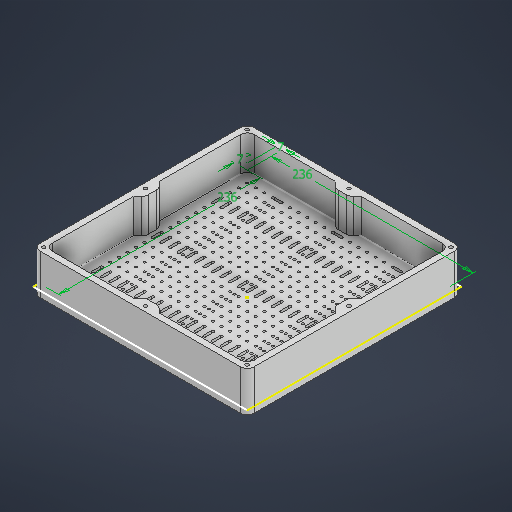
# Autodesk Inventor part: Part1
Saved by Autodesk Inventor 2027.2 (Build 312334000, 334)
## iProperties
Created: 2026-11-18
Part Number: Part1
Material: Generic
Document SubType Name: Modeling
Designer: Brian Wang
Density: 1 g/cm^3
Appearance: Default
Author: Brian Wang
Autodesk Inventor part; units mm, degrees
ref_plane "YZ Plane" through (0, 0, 0) normal (1, 0, 0) x (0, 1, 0)
ref_plane "XZ Plane" through (0, 0, 0) normal (0, 1, 0) x (-1, 0, 0)
ref_plane "XY Plane" through (0, 0, 0) normal (0, 0, 1) x (1, 0, 0)
sketch "Sketch1" plane through (0, 0, 0) normal (0, 1, 0) x (-1, 0, 0)
  line L0 (136.8407, 113.2957) -> (-113.1593, 113.2957)
  line L1 (-113.1593, 113.2957) -> (-113.1593, -136.7043) construction
  line L2 (-113.1593, -136.7043) -> (136.8407, -136.7043)
  line L3 (136.8407, -136.7043) -> (136.8407, 113.2957)
  line L4 (-113.1593, 113.2957) -> (-113.1593, -136.7043)
  point P0 (0, 0)
  dimension "d0" = 250
  dimension "d1" = 250
  constraints: 10 end point, 3 equal length, 1 horizontal, 1 perpendicular
  measures "d0" distance of L2.end L1.end
  measures "d1" distance of L1.end L0.end
extrude "Extrusion1" add sketch "Sketch1" along normal blind 7
sketch "Sketch2" plane through (0, 7, 0) normal (0, 1, 0) x (1, 0, 0)
  point P0 (0, 0)
sketch "Sketch3" plane through (0, 7, 0) normal (0, 1, 0) x (1, 0, 0)
  line L0 (-136.8407, 136.7043) -> (-136.8407, -113.2957) projected
  line L1 (113.1593, -113.2957) -> (113.1593, 136.7043) projected
  line L2 (-136.8407, -113.2957) -> (113.1593, -113.2957)
  line L3 (113.1593, -113.2957) -> (113.1593, 136.7043)
  line L4 (113.1593, 136.7043) -> (-136.8407, 136.7043)
  line L5 (-136.8407, 136.7043) -> (-136.8407, -113.2957)
  line L6 (-129.8407, -106.2957) -> (106.1593, -106.2957)
  line L7 (106.1593, -106.2957) -> (106.1593, 129.7043)
  line L8 (106.1593, 129.7043) -> (-129.8407, 129.7043)
  line L9 (-129.8407, 129.7043) -> (-129.8407, -106.2957)
  point P0 (0, 0)
  dimension "d4" = 236
  dimension "d5" = 236
  dimension "d6" = 7
  dimension "d7" = 7
  constraints: 16 end point, 4 parallel, 2 horizontal, 2 perpendicular
  measures "d4" distance of L7.end L8.end
  measures "d5" distance of L8.end L6.start
  measures "d6" distance between parallel lines of L0 L9
  measures "d7" distance between parallel lines of L4 L8
extrude "Extrusion2" add sketch "Sketch3" along normal blind 40
fillet "Fillet1" radius 8 4 edges at (113.1593, 23.5, 113.2957) (113.1593, 23.5, -136.7043) (-136.8407, 23.5, -136.7043) (-136.8407, 23.5, 113.2957)
fillet "Face Fillet1" radius 8 1 edges at (-129.8407, 27, -129.7043)
fillet "Face Fillet2" radius 8 1 edges at (106.1593, 27, -129.7043)
fillet "Face Fillet3" radius 8 1 edges at (106.1593, 27, 106.2957)
fillet "Face Fillet4" radius 8 1 edges at (-129.8407, 27, 106.2957)
sketch "Sketch5" plane through (0, 47, 0) normal (0, 1, 0) x (1, 0, 0)
  circle A0 centre (-130.8407, 130.7043) radius 2
  circle A1 centre (-130.8407, -107.2957) radius 2
  circle A2 centre (107.1593, -107.2957) radius 2
  circle A3 centre (107.1593, 130.7043) radius 2
  line L0 (-128.8407, -113.2957) -> (105.1593, -113.2957) projected
  line L1 (-136.8407, 128.7043) -> (-136.8407, -105.2957) projected
  line L2 (105.1593, 136.7043) -> (-128.8407, 136.7043) projected
  line L3 (113.1593, -105.2957) -> (113.1593, 128.7043) projected
  point P0 (0, 0)
  dimension "d23" = 4
  dimension "d24" = 4
  dimension "d25" = 4
  dimension "d26" = 4
  dimension "d32" = 6
  dimension "d33" = 6
  dimension "d34" = 6
  dimension "d35" = 6
  dimension "d36" = 6
  dimension "d37" = 6
  dimension "d38" = 6
  dimension "d39" = 6
  constraints: 4 centre point
  measures "d23" diameter of A0
  measures "d24" diameter of A1
  measures "d25" diameter of A2
  measures "d26" diameter of A3
  measures "d32" distance from line of L0 A1.centre
  measures "d33" distance from line of L1 A1.centre
  measures "d34" distance from line of L1 A0.centre
  measures "d35" distance from line of L2 A0.centre
  measures "d36" distance from line of L2 A3.centre
  measures "d37" distance from line of L3 A3.centre
  measures "d38" distance from line of L3 A2.centre
  measures "d39" distance from line of L0 A2.centre
sketch "Sketch6" plane through (0, 7, 0) normal (0, 1, 0) x (1, 0, 0)
  line L0 (-129.8407, 121.7043) -> (-129.8407, -98.2957) projected
  line L1 (-129.8407, 26.7043) -> (-122.8407, 26.7043)
  line L2 (-122.8407, 26.7043) -> (-122.8407, -3.2957)
  line L3 (-122.8407, -3.2957) -> (-129.8407, -3.2957)
  line L4 (-129.8407, -3.2957) -> (-129.8407, 26.7043)
  line L5 (98.1593, 129.7043) -> (-121.8407, 129.7043) projected
  line L6 (-26.8407, 129.7043) -> (3.1593, 129.7043)
  line L7 (3.1593, 129.7043) -> (3.1593, 122.7043)
  line L8 (3.1593, 122.7043) -> (-26.8407, 122.7043)
  line L9 (-26.8407, 122.7043) -> (-26.8407, 129.7043)
  line L10 (106.1593, -98.2957) -> (106.1593, 121.7043) projected
  line L11 (106.1593, 26.7043) -> (99.1593, 26.7043)
  line L12 (99.1593, 26.7043) -> (99.1593, -3.2957)
  line L13 (99.1593, -3.2957) -> (106.1593, -3.2957)
  line L14 (106.1593, -3.2957) -> (106.1593, 26.7043)
  line L15 (-121.8407, -106.2957) -> (98.1593, -106.2957) projected
  line L16 (3.1593, -106.2957) -> (-26.8407, -106.2957)
  line L17 (-26.8407, -106.2957) -> (-26.8407, -99.2957)
  line L18 (-26.8407, -99.2957) -> (3.1593, -99.2957)
  line L19 (3.1593, -99.2957) -> (3.1593, -106.2957)
  line L20 (-136.8407, 128.7043) -> (-136.8407, -105.2957) projected
  line L21 (105.1593, 136.7043) -> (-128.8407, 136.7043) projected
  line L22 (-128.8407, -113.2957) -> (105.1593, -113.2957) projected
  point P0 (0, 0)
  point P1 (-26.8407, 126.2043)
  point P2 (102.6593, 26.7043)
  point P3 (-126.3407, 26.7043)
  point P4 (102.6593, -3.2957)
  dimension "d40" = 7
  dimension "d41" = 30
  dimension "d42" = 30
  dimension "d43" = 7
  dimension "d44" = 7
  dimension "d45" = 30
  dimension "d46" = 7
  dimension "d48" = 110
  dimension "d49" = 110
  dimension "d50" = 110
  dimension "d51" = 110
  constraints: 32 end point, 8 parallel, 5 point on line, 4 horizontal, 4 midpoint, 4 perpendicular
  measures "d40" distance of L2.end L3.end
  measures "d41" distance of L1.end L2.end
  measures "d42" distance of L7.end L8.end
  measures "d43" distance of L6.end L7.end
  measures "d44" distance of L13.end L12.end
  measures "d45" distance of L17.end L18.end
  measures "d46" distance of L16.end L17.end
  measures "d48" distance from line of L20 point (-26.841, 126.204)
  measures "d49" distance from line of L21 point (102.659, 26.704)
  measures "d50" distance from line of L21 point (-126.341, 26.704)
  measures "d51" distance from line of L22 point (102.659, -3.296)
extrude "Extrusion4" add sketch "Sketch6" along normal blind 40
extrude "Extrusion5" cut sketch "Sketch5" against normal blind 8
sketch "Sketch7" plane through (0, 47, 0) normal (0, 1, 0) x (1, 0, 0)
  circle A0 centre (-130.8407, 11.7043) radius 2
  circle A1 centre (-11.8407, 130.7043) radius 2
  circle A2 centre (107.1593, 11.7043) radius 2
  circle A3 centre (-11.8407, -107.2957) radius 2
  line L0 (-136.8407, 128.7043) -> (-136.8407, -105.2957) projected
  line L1 (105.1593, 136.7043) -> (-128.8407, 136.7043) projected
  line L2 (113.1593, -105.2957) -> (113.1593, 128.7043) projected
  line L3 (-128.8407, -113.2957) -> (105.1593, -113.2957) projected
  point P0 (0, 0)
  point P1 (-11.8407, 136.7043)
  dimension "d56" = 4
  dimension "d57" = 4
  dimension "d58" = 4
  dimension "d59" = 4
  dimension "d60" = 6
  dimension "d61" = 6
  dimension "d62" = 6
  dimension "d63" = 6
  constraints: 4 centre point, 1 midpoint
  measures "d56" diameter of A0
  measures "d57" diameter of A1
  measures "d58" diameter of A2
  measures "d59" diameter of A3
  measures "d60" distance from line of L0 A0.centre
  measures "d61" distance of point (-11.841, 136.704) A1.centre
  measures "d62" distance from line of L2 A2.centre
  measures "d63" distance from line of L3 A3.centre
extrude "Extrusion6" cut sketch "Sketch7" against normal blind 8
chamfer "Chamfer1" distance 7 angle 45 8 edges at (-122.8407, 27, 3.2957) (-122.8407, 27, -26.7043) (3.1593, 27, -122.7043) (-26.8407, 27, -122.7043) (99.1593, 27, 3.2957) (99.1593, 27, -26.7043) (-26.8407, 27, 99.2957) (3.1593, 27, 99.2957)
fillet "Fillet2" radius 8 8 edges at (99.1593, 27, -19.7044) (99.1593, 27, -3.7042) (-19.8408, 27, 99.2957) (-3.8406, 27, 99.2957) (-122.8407, 27, -19.7044) (-122.8407, 27, -3.7042) (-19.8408, 27, -122.7043) (-3.8406, 27, -122.7043)
sketch "Sketch8" plane through (0, 7, 0) normal (0, 1, 0) x (1, 0, 0)
  line L0 (-121.8407, -98.2957) -> (98.4953, -98.2957)
  line L1 (98.4953, -98.2957) -> (98.4953, 121.7043)
  line L2 (98.4953, 121.7043) -> (-121.8407, 121.7043)
  line L3 (-121.8407, 121.7043) -> (-121.8407, -98.2957)
  line L4 (-128.8407, -113.2957) -> (105.1593, -113.2957) projected
  line L5 (-136.8407, 128.7043) -> (-136.8407, -105.2957) projected
  circle A0 centre (-116.8407, -93.2957) radius 1.45
  point P0 (0, 0)
  dimension "d70" = 220
  dimension "d71" = 15
  dimension "d72" = 15
  dimension "d73" = 2.9
  dimension "d74" = 5
  dimension "d75" = 5
  constraints: 8 end point, 2 parallel, 1 centre point, 1 horizontal, 1 perpendicular
  measures "d70" distance of L2.end L0.start
  measures "d71" distance between parallel lines of L4 L0
  measures "d72" distance between parallel lines of L5 L3
  measures "d73" diameter of A0
  measures "d74" distance from line of L3 A0.centre
  measures "d75" distance from line of L0 A0.centre
extrude "Extrusion7" cut sketch "Sketch8" against normal through all contours A0
pattern_linear "Rectangular Pattern1" count 22 spacing 10 along (1, 0, 0) count 22 spacing 10 along (0, 0, -1) of "Extrusion7"
sketch "Sketch9" plane through (0, 7, 0) normal (0, 1, 0) x (1, 0, 0)
  circle A0 centre (-81.8407, -93.2957) radius 1.45
  circle A1 centre (-86.8407, -93.2957) radius 1.45 projected
  point P0 (0, 0)
  dimension "d84" = 2.9
  dimension "d85" = 5
  constraints: 1 centre point
  measures "d84" diameter of A0
  measures "d85" distance of A1.centre A0.centre
extrude "Extrusion8" cut sketch "Sketch9" against normal through all contours A0
pattern_linear "Rectangular Pattern2" count 22 spacing 10 along (0, 0, -1) of "Extrusion8"
sketch "Sketch10" plane through (0, 7, 0) normal (0, 1, 0) x (1, 0, 0)
  circle A0 centre (58.1593, -93.2957) radius 1.45
  circle A1 centre (63.1593, -93.2957) radius 1.45 projected
  point P0 (0, 0)
  dimension "d91" = 2.9
  dimension "d92" = 5
  constraints: 1 centre point
  measures "d91" diameter of A0
  measures "d92" distance of A1.centre A0.centre
extrude "Extrusion9" cut sketch "Sketch10" against normal through all contours A0
pattern_linear "Rectangular Pattern3" count 22 spacing 10 along (0, 0, -1) of "Extrusion9"
sketch "Sketch11" plane through (0, 7, 0) normal (0, 1, 0) x (1, 0, 0)
  circle A0 centre (-11.8407, -93.2957) radius 1.45
  circle A1 centre (-16.8407, -93.2957) radius 1.45 projected
  point P0 (0, 0)
  dimension "d98" = 2.9
  dimension "d99" = 5
  constraints: 1 centre point
  measures "d98" diameter of A0
  measures "d99" distance of A1.centre A0.centre
extrude "Extrusion10" cut sketch "Sketch11" against normal through all contours A0
pattern_linear "Rectangular Pattern4" count 22 spacing 10 along (0, 0, -1) of "Extrusion10"
sketch "Sketch12" plane through (0, 7, 0) normal (0, 1, 0) x (1, 0, 0)
  circle A0 centre (-116.8407, -58.2957) radius 1.45
  circle A1 centre (-116.8407, -63.2957) radius 1.45 projected
  circle A2 centre (-116.8407, 11.7043) radius 1.45
  circle A3 centre (-116.8407, 16.7043) radius 1.45 projected
  circle A4 centre (-116.8407, 81.7043) radius 1.45
  circle A5 centre (-116.8407, 86.7043) radius 1.45 projected
  point P0 (0, 0)
  dimension "d105" = 2.9
  dimension "d106" = 5
  dimension "d107" = 2.9
  dimension "d108" = 5
  dimension "d109" = 2.9
  dimension "d110" = 5
  constraints: 3 centre point
  measures "d105" diameter of A0
  measures "d106" distance of A1.centre A0.centre
  measures "d107" diameter of A2
  measures "d108" distance between centres of A3 A2
  measures "d109" diameter of A4
  measures "d110" distance of A5.centre A4.centre
extrude "Extrusion11" cut sketch "Sketch12" against normal through all contours A0 | A2 | A4
pattern_linear "Rectangular Pattern5" count 22 spacing 10 along (1, 0, 0) of "Extrusion11"
sketch "Sketch13" plane through (0, 7, 0) normal (0, 1, 0) x (1, 0, 0)
  circle A0 centre (-116.8407, 86.7043) radius 1.45 projected
  line L0 (-115.3907, 86.7043) -> (-115.3907, 76.7043)
  circle A1 centre (-116.8407, 76.7043) radius 1.45 projected
  line L1 (-118.3007, 86.7043) -> (-118.3007, 76.7043)
  arc A2 (-115.3907, 86.7043) -> (-118.3007, 86.7043) centre (-116.8457, 86.7043) ccw
  arc A3 (-118.3007, 76.7043) -> (-115.3907, 76.7043) centre (-116.8457, 76.7043) ccw
  circle A4 centre (-116.8407, 16.7043) radius 1.45 projected
  line L2 (-115.3907, 16.7043) -> (-115.3907, 6.7043)
  circle A5 centre (-116.8407, 6.7043) radius 1.45 projected
  line L3 (-118.3007, 16.7043) -> (-118.3007, 6.7043)
  arc A6 (-115.3907, 16.7043) -> (-118.3007, 16.7043) centre (-116.8457, 16.7043) ccw
  arc A7 (-118.3007, 6.7043) -> (-115.3907, 6.7043) centre (-116.8457, 6.7093) ccw
  circle A8 centre (-116.8407, -53.2957) radius 1.45 projected
  line L4 (-115.3907, -53.2957) -> (-115.3907, -63.2957)
  circle A9 centre (-116.8407, -63.2957) radius 1.45 projected
  line L5 (-118.3007, -53.2957) -> (-118.3007, -63.2957)
  arc A10 (-115.3907, -53.2957) -> (-118.3007, -53.2957) centre (-116.8457, -53.2957) ccw
  arc A11 (-118.3007, -63.2957) -> (-115.3907, -63.2957) centre (-116.8457, -63.2957) ccw
  point P0 (0, 0)
  point P1 (-116.8407, 5.2543)
  constraints: 12 end point, 12 point on circle, 10 tangent, 6 centre point, 6 vertical, 5 horizontal alignment, 7 other
extrude "Extrusion12" cut sketch "Sketch13" against normal through all contours L0 A3 L1 A2 | L2 A5 A7 L3 A6 | L4 A11 L5 A10
pattern_linear "Rectangular Pattern6" count 22 spacing 10 along (1, 0, 0) of "Extrusion12"
sketch "Sketch14" plane through (0, 7, 0) normal (0, 1, 0) x (1, 0, 0)
  circle A0 centre (-86.8407, 116.7043) radius 1.45 projected
  line L0 (-86.8407, 118.1543) -> (-76.8407, 118.1543)
  circle A1 centre (-76.8407, 116.7043) radius 1.45 projected
  line L1 (-76.8407, 115.2543) -> (-86.8407, 115.2543)
  arc A2 (-86.8407, 118.1543) -> (-86.8407, 115.2543) centre (-86.8407, 116.7043) ccw
  arc A3 (-76.8407, 115.2543) -> (-76.8407, 118.1543) centre (-76.8407, 116.7043) ccw
  circle A4 centre (-16.8407, 116.7043) radius 1.45 projected
  arc A5 (-16.8407, 118.1543) -> (-16.8407, 115.2543) centre (-16.8407, 116.7043) ccw
  circle A6 centre (-6.8407, 116.7043) radius 1.45 projected
  arc A7 (-6.8407, 115.2543) -> (-6.8407, 118.1543) centre (-6.8407, 116.7043) ccw
  line L2 (-16.8407, 118.1543) -> (-6.8407, 118.1543)
  line L3 (-16.8407, 115.2543) -> (-6.8407, 115.2543)
  circle A8 centre (53.1593, 116.7043) radius 1.45 projected
  arc A9 (53.1593, 118.1543) -> (53.1593, 115.2543) centre (53.1593, 116.7043) ccw
  circle A10 centre (63.1593, 116.7043) radius 1.45 projected
  arc A11 (63.1593, 115.2543) -> (63.1593, 118.1543) centre (63.1593, 116.7043) ccw
  line L4 (53.1593, 118.1543) -> (63.1593, 118.1543)
  line L5 (53.1593, 115.2543) -> (63.1593, 115.2543)
  point P0 (0, 0)
  constraints: 22 point on circle, 15 tangent, 12 end point, 6 centre point, 3 horizontal, 2 parallel, 2 other
extrude "Extrusion13" cut sketch "Sketch14" against normal through all
body "Solid1"
